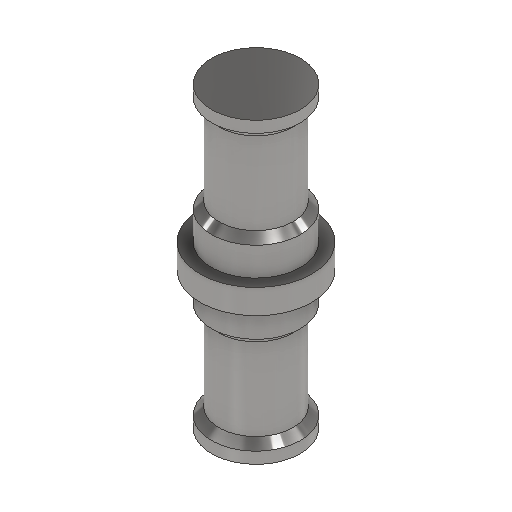
# Autodesk Inventor part: COTS_GlareOne_A-275_Tripod_Mounting_Shaft
Saved by Autodesk Inventor 2027 (Build 310192060, 192F)
## iProperties
Created: 2025-05-09
Part Number: COTS_GlareOne_A-275_Tripod_Mounting_Shaft
Material: Generic
Document SubType Name: Modeling
Designer: User
Density: 1 g/cm^3
Appearance: Steel - Polished
Author: User
Autodesk Inventor part; units mm, degrees
ref_plane "YZ Plane" through (0, 0, 0) normal (1, 0, 0) x (0, 1, 0)
ref_plane "XZ Plane" through (0, 0, 0) normal (0, 1, 0) x (-1, 0, 0)
ref_plane "XY Plane" through (0, 0, 0) normal (0, 0, 1) x (1, 0, 0)
sketch "Sketch1" plane through (0, 0, 0) normal (0, 0, 1) x (1, 0, 0)
  line L0 (0, 0) -> (7.8, 0)
  line L1 (7.8, 0) -> (7.8, -2)
  line L2 (7.8, -2) -> (7.8, -2)
  line L3 (6.5, -3.3) -> (6.5, -17.7)
  line L4 (7.8, -19) -> (7.8, -19)
  line L5 (7.8, -19) -> (7.8, -24)
  line L6 (7.8, -24) -> (9.8, -24)
  line L7 (9.8, -24) -> (9.8, -28.3)
  line L8 (9.8, -28.3) -> (7.8, -28.3)
  line L9 (7.8, -28.3) -> (7.8, -33.3)
  line L10 (7.8, -33.3) -> (7.8, -33.3)
  line L11 (6.5, -34.6) -> (6.5, -49)
  line L12 (7.8, -50.3) -> (7.8, -50.3)
  line L13 (7.8, -50.3) -> (7.8, -52.3)
  line L14 (7.8, -52.3) -> (0, -52.3)
  line L15 (7.8, -2) -> (6.5, -3.3)
  line L16 (6.5, -17.7) -> (7.8, -19)
  line L17 (6.5, -34.6) -> (7.8, -33.3)
  line L18 (6.5, -49) -> (7.8, -50.3)
  line L19 (0, 0) -> (0, -52.3)
  line L20 (0, -62.76) -> (0, 10.46) projected
  point P0 (6.5, -2)
  point P1 (6.5, -19)
  point P2 (6.5, -33.3)
  point P3 (6.5, -50.3)
  dimension "d0" = 7.8
  dimension "d1" = 2
  dimension "d2" = 17
  dimension "d3" = 17
  dimension "d4" = 5
  dimension "d5" = 5
  dimension "d6" = 4.3
  dimension "d7" = 2
  dimension "d8" = 7.8
  dimension "d9" = 6.5
  dimension "d10" = 6.5
  dimension "d11" = 9.8
  dimension "d12" = 1.3
  dimension "d13" = 1.3
  dimension "d14" = 1.3
  dimension "d15" = 1.3
  dimension "d16" = 1.3
  dimension "d17" = 1.3
  dimension "d18" = 1.3
  dimension "d19" = 1.3
  constraints: 40 end point, 16 point on line, 10 perpendicular, 1 coincident, 1 horizontal
  measures "d0" distance of L0.start L0.end
  measures "d1" distance of L0.end L1.end
  measures "d2" distance of point (6.5, -2) point (6.5, -19)
  measures "d3" distance of point (6.5, -33.3) point (6.5, -50.3)
  measures "d4" distance between parallel lines of L6 L4
  measures "d5" distance between parallel lines of L10 L8
  measures "d6" distance between parallel lines of L8 L6
  measures "d7" distance between parallel lines of L12 L14
  measures "d8" distance of L13.end L14.end
  measures "d9" distance from line of point (0, 0) L3
  measures "d10" distance from line of point (0, 0) L11
  measures "d11" distance from line of point (0, 0) L7
  measures "d12" distance of L2.end point (6.5, -2)
  measures "d13" distance of L3.start point (6.5, -2)
  measures "d14" distance of L3.end point (6.5, -19)
  measures "d15" distance of L4.start point (6.5, -19)
  measures "d16" distance of L11.start point (6.5, -33.3)
  measures "d17" distance of L10.end point (6.5, -33.3)
  measures "d18" distance of L11.end point (6.5, -50.3)
  measures "d19" distance of L12.start point (6.5, -50.3)
revolve "Revolution1" add sketch "Sketch1" angle 360 about axis through (0, -10, 0) along (0, 1, 0)
equation "\"d5\" = d4"
equation "\"d8\" = d0"
equation "\"d13\" = d12"
equation "\"d14\" = d12"
equation "\"d15\" = d14"
equation "\"d16\" = d12"
equation "\"d17\" = d16"
equation "\"d18\" = d12"
equation "\"d19\" = d18"
body "Solid1"
